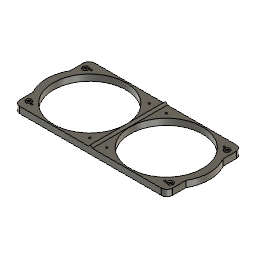
porsche-911-f-model-dash-double-front-speaker (Autodesk Fusion 360 design; units mm, degrees)
part number: 2026-11-07-18-49-33-009
Autodesk Fusion 360 part; units mm, degrees
sketch "01 Base outline" plane through (0, 0, 0) normal (0, 0, 1) x (1, 0, 0)
  line L0 (-100, 53) -> (100, 53)
  arc A0 (108, 45) -> (100, 53) centre (100, 45) ccw
  line L1 (108, 45) -> (108, 26.192)
  arc A1 (108, -26.192) -> (108, 26.192) centre (62.5, 0) ccw
  line L2 (108, -26.192) -> (108, -45)
  arc A2 (100, -53) -> (108, -45) centre (100, -45) ccw
  line L3 (100, -53) -> (-100, -53)
  arc A3 (-108, -45) -> (-100, -53) centre (-100, -45) ccw
  line L4 (-108, -45) -> (-108, -26.192)
  arc A4 (-108, 26.192) -> (-108, -26.192) centre (-62.5, 0) ccw
  line L5 (-108, 26.192) -> (-108, 45)
  arc A5 (-100, 53) -> (-108, 45) centre (-100, 45) ccw
extrude "02 Extrude base plate 9 mm" add sketch "01 Base outline" along normal blind 9
sketch "Sketch2" plane through (0, 0, 0) normal (0, 0, 1) x (1, 0, 0)
  circle A0 centre (-54, 0) radius 51
  circle A1 centre (54, 0) radius 51
extrude "04 Cut speaker openings" cut sketch "Sketch2" along normal through all
sketch "05 All through holes" plane through (0, 0, 0) normal (0, 0, 1) x (1, 0, 0)
  circle A0 centre (-100, -40) radius 2
  circle A1 centre (-100, 40) radius 2
  circle A2 centre (100, -40) radius 2
  circle A3 centre (100, 40) radius 2
  circle A4 centre (-12, -42) radius 1.3
  circle A5 centre (-12, 42) radius 1.3
  circle A6 centre (12, -42) radius 1.3
  circle A7 centre (12, 42) radius 1.3
  circle A8 centre (-94, -42) radius 1.3
  circle A9 centre (-94, 42) radius 1.3
  circle A10 centre (94, -42) radius 1.3
  circle A11 centre (94, 42) radius 1.3
extrude "06 Cut mounting holes" cut sketch "05 All through holes" along normal through all
ref_plane "WorkPlane1" through (0, 0, 7) normal (0, 0, 1) x (1, 0, 0)
sketch "Sketch4" plane through (0, 0, 7) normal (0, 0, 1) x (1, 0, 0)
  circle A0 centre (-100, -40) radius 4
  circle A1 centre (-100, 40) radius 4
  circle A2 centre (100, -40) radius 4
  circle A3 centre (100, 40) radius 4
extrude "08 Cut counterbores 2 mm deep" cut sketch "Sketch4" along normal blind 2
sketch "09 Centre rib profile" plane through (0, 0, 0) normal (0, 1, 0) x (1, 0, 0)
  line L0 (-2.8, -8.8) -> (0, -12)
  line L1 (0, -12) -> (2.8, -8.8)
  line L2 (2.8, -8.8) -> (-2.8, -8.8)
  dimension "d21" = 0
extrude "10 Extrude centre rib" add sketch "09 Centre rib profile" along normal mid plane 106
equation "plateThickness = 9.0 mm" comment "Base plate thickness"
equation "overallWidth = 230.0 mm" comment "Overall width"
equation "overallHeight = 106.0 mm" comment "Overall height"
equation "speakerDiameter = 102.0 mm" comment "Speaker opening diameter"
equation "speakerSpacing = 108.0 mm" comment "Speaker centre spacing"
equation "outerHoleDiameter = 4.0 mm" comment "Outer mounting holes"
equation "counterboreDiameter = 8.0 mm" comment "Outer recess diameter"
equation "counterboreDepth = 2.0 mm" comment "Outer recess depth"
equation "innerHoleDiameter = 2.6 mm" comment "Inner mounting holes"
equation "speakerMountHoleDiameter = 2.6 mm" comment "Speaker mounting holes"
equation "ribHeight = 3.0 mm" comment "Centre rib height"
named bodies: "Speaker adapter plate"
